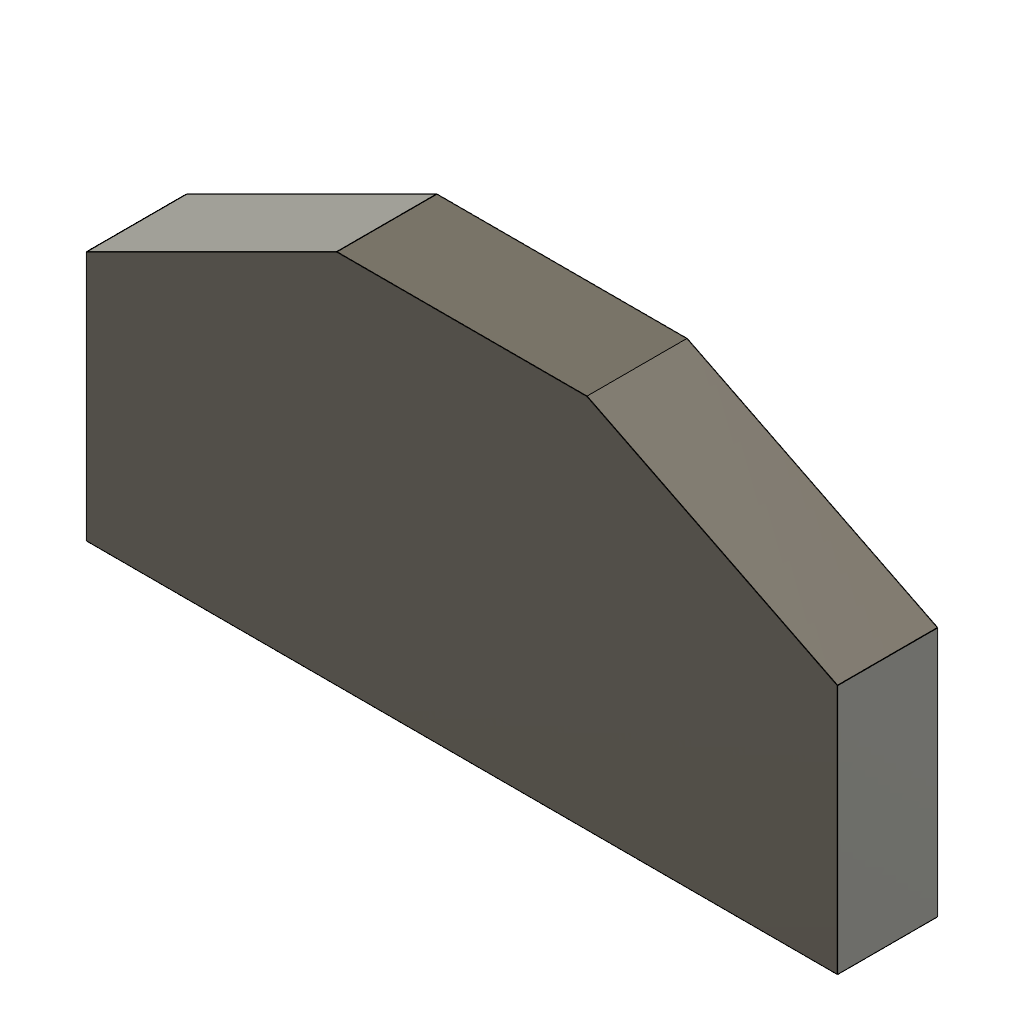
sk_mirror_in_sketch (Autodesk Fusion 360 design; units mm, degrees)
part number: 2026-11-13-14-36-25-110
Autodesk Fusion 360 part; units mm, degrees
sketch "Sketch1" plane through (0, 0, 0) normal (0, 0, 1) x (1, 0, 0)
  line L0 (0, -20) -> (0, 20) construction
  line L1 (0, 0) -> (15, 0)
  line L2 (15, 0) -> (15, 10)
  line L3 (15, 10) -> (5, 15)
  line L4 (5, 15) -> (0, 15)
  line L5 (0, 15) -> (0, 0) construction
  line L6 (0, 0) -> (-15, 0)
  line L7 (-15, 0) -> (-15, 10)
  line L8 (-15, 10) -> (-5, 15)
  line L9 (-5, 15) -> (0, 15)
  constraint symmetric L0 L1.start L5.end
  constraint symmetric L0 L1.end L6.end
  constraint symmetric L0 L2.end L7.end
  constraint symmetric L0 L3.end L8.end
  constraint symmetric L0 L4.end L5.start
extrude "Extrude1" add sketch "Sketch1" along normal blind 4
